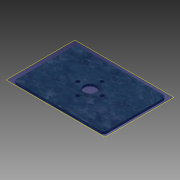
# Autodesk Inventor part: GoPro_Mount_Back
Saved by Autodesk Inventor 2013 (Build 170138000, 138)
## iProperties
Created: 2013-09-30
Part Number: GoPro_Mount_Back
Material: Generic
Document SubType Name: Modeling
Designer: Jeff
Density: 1 g/cm^3
Author: Jeff
Autodesk Inventor part; units mm, degrees
ref_plane "YZ Plane" through (0, 0, 0) normal (1, 0, 0) x (0, 1, 0)
ref_plane "XZ Plane" through (0, 0, 0) normal (0, 1, 0) x (-1, 0, 0)
ref_plane "XY Plane" through (0, 0, 0) normal (0, 0, 1) x (1, 0, 0)
ref_plane "Work Plane1" through (0.8405, -25.6794, -41.2863) normal (0, 0, -1) x (-1, 0, 0)
sketch "Sketch1" plane through (0.8405, -25.6794, -41.2863) normal (0, 0, -1) x (-1, 0, 0)
  line L0 (27.625, 20.6) -> (-27.625, 20.6) projected
  line L1 (-29.625, 18.6) -> (-29.625, -18.6) projected
  line L2 (29.625, 15.1) -> (29.625, -15.1) projected
  line L3 (-27.625, -20.6) -> (27.625, -20.6) projected
  line L4 (-27.625, 20.6) -> (27.625, 20.6)
  line L5 (29.625, 18.6) -> (29.625, -18.6)
  line L6 (27.625, -20.6) -> (-27.625, -20.6)
  line L7 (-29.625, -18.6) -> (-29.625, 18.6)
  arc A0 (-27.625, 20.6) -> (-29.625, 18.6) centre (-27.625, 18.6) ccw
  arc A1 (-29.625, -18.6) -> (-27.625, -20.6) centre (-27.625, -18.6) ccw
  arc A2 (27.625, -20.6) -> (29.625, -18.6) centre (27.625, -18.6) ccw
  arc A3 (29.625, 18.6) -> (27.625, 20.6) centre (27.625, 18.6) ccw
  line L8 (-29.625, 0) -> (29.625, 0)
  line L9 (0, -20.6) -> (0, 20.6)
  circle A4 centre (8, 0) radius 1.25
  circle A5 centre (0, 8) radius 1.25
  circle A6 centre (-8, 0) radius 1.25
  circle A7 centre (0, -8) radius 1.25
  circle A8 centre (-0.0004, 0) radius 4
  point P0 (0.8405, 25.6794)
  point P1 (-9.5005, 0)
  point P2 (0, 0)
  dimension "d0" = 2
  dimension "d1" = 2.5
  dimension "d2" = -16
  dimension "d5" = 360
  dimension "d9" = 8
  constraints: 12 end point, 9 centre point, 8 point on circle, 8 tangent, 3 equal radius, 2 horizontal, 2 parallel, 1 perpendicular, 1 vertical, 1 other
  measures "d0" radius of A0
  measures "d1" diameter of A4
  measures "d2" diameter of A4.centre L9
  measures "d9" diameter of A8
extrude "Extrusion2" add sketch "Sketch1" along normal blind 1.5875 contours A3 L5 L2 L8 A4 A8 L9 A5 L0 | L9 A5 A8 L8 A6 L1 A0 L0 | L2 L5 A2 L3 L9 A7 A8 L8 A4 | L8 A6 A8 L9 A7 L3 A1 L1
body "Solid2"
